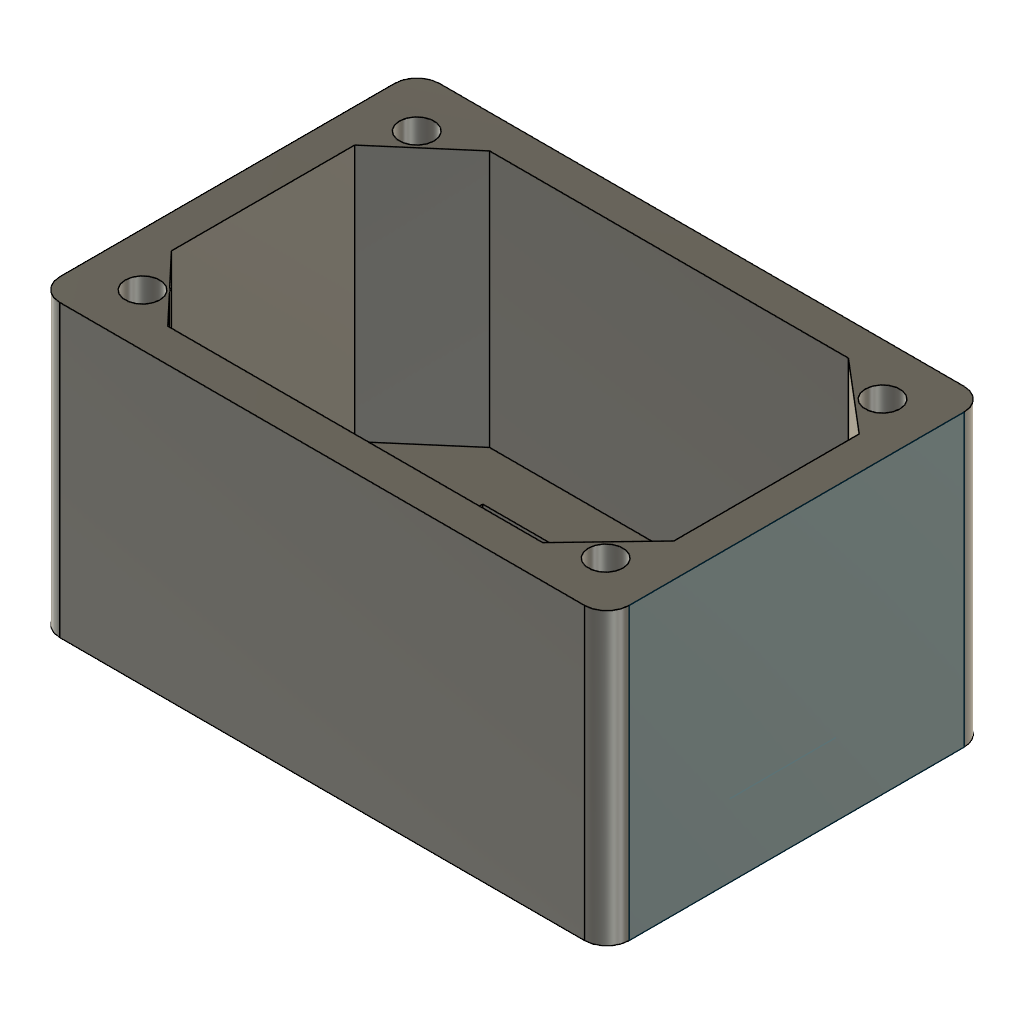
oled keychain (Autodesk Fusion 360 design; units mm, degrees)
Autodesk Fusion 360 part; units mm, degrees
sketch "Sketch1" plane through (0, 0, 0) normal (0, 0, 1) x (1, 0, 0)
  line L0 (0, 0) -> (51, 0)
  line L1 (51, 0) -> (51, 34)
  line L2 (51, 34) -> (0, 34)
  line L3 (0, 34) -> (0, 0)
  dimension "d1" = 51
  dimension "d2" = 34
  constraint horizontal L0
  constraint vertical L1
  constraint horizontal L2
  constraint vertical L3
  constraint coincident L0.start L3.end
  measures "d1" distance of L0.start L0.end
  measures "d2" distance of L0.start L2.end
extrude "Extrude1" add sketch "Sketch1" along normal blind 3
sketch "Sketch2" plane through (0, 0, 3) normal (0, 0, 1) x (-1, 0, 0)
  line L0 (0, -34) -> (0, 0)
  line L1 (0, 0) -> (-51, 0)
  line L2 (-51, 0) -> (-51, -34)
  line L3 (-51, -34) -> (0, -34)
  line L4 (0, -34) -> (-51, -34)
  line L5 (-51, -34) -> (-51, -31)
  line L6 (-51, -31) -> (0, -31)
  line L7 (0, -31) -> (0, -34)
  line L8 (0, 0) -> (-51, 0)
  line L9 (-51, 0) -> (-51, -3)
  line L10 (-51, -3) -> (0, -3)
  line L11 (0, -3) -> (0, 0)
  line L12 (0, -31) -> (-3, -31)
  line L13 (-3, -31) -> (-3, -3)
  line L14 (-3, -3) -> (0, -3)
  line L15 (0, -3) -> (0, -31)
  line L16 (-51, -31) -> (-48, -31)
  line L17 (-48, -31) -> (-48, -3)
  line L18 (-48, -3) -> (-51, -3)
  line L19 (-51, -3) -> (-51, -31)
  dimension "d5" = 3
  dimension "d6" = 3
  constraint horizontal L4
  constraint vertical L5
  constraint horizontal L6
  constraint vertical L7
  constraint coincident L0.start L3.end
  constraint horizontal L8
  constraint vertical L9
  constraint horizontal L10
  constraint vertical L11
  constraint coincident L0.end L1.start
  constraint horizontal L12
  constraint vertical L13
  constraint horizontal L14
  constraint vertical L15
  constraint coincident L10 L13.end
  constraint horizontal L16
  constraint vertical L17
  constraint horizontal L18
  constraint vertical L19
  constraint coincident L10 L17.end
  measures "d5" distance of L0.start L6.end
  measures "d6" distance of L0.end L10.end
extrude "Extrude2" add sketch "Sketch2" along normal blind 23 contours L0 L2 L3 L4 L5 L6 L7 L12 L16 | L0 L6 L10 L12 L13 L14 L15 | L0 L1 L2 L8 L9 L10 L11 L14 L18 | L2 L6 L10 L16 L17 L18 L19
fillet "Fillet1" radius 2 1 edges at (51, 0, 13)
fillet "Fillet2" radius 2 1 edges at (51, 34, 13)
fillet "Fillet3" radius 2 1 edges at (0, 34, 13)
fillet "Fillet4" radius 2 1 edges at (0, 0, 13)
fillet "Fillet5" radius 2 1 edges at (48, 31, 14.5)
fillet "Fillet6" radius 2 1 edges at (48, 3, 14.5)
fillet "Fillet7" radius 2 1 edges at (3, 3, 14.5)
fillet "Fillet8" radius 2 1 edges at (3, 31, 14.5)
sketch "Sketch3" plane through (51, 0, 0) normal (1, 0, 0) x (0, 1, 0)
  line L0 (32, 0) -> (32, 26)
  line L1 (32, 26) -> (2, 26)
  line L2 (2, 26) -> (2, 0)
  line L3 (2, 0) -> (32, 0)
sketch "Sketch4" plane through (0, 0, 3) normal (0, 0, 1) x (-1, 0, 0)
  arc A0 (-5, -31) -> (-3, -29) centre (-5, -29) ccw
  line L0 (-3, -29) -> (-3, -5)
  arc A1 (-3, -5) -> (-5, -3) centre (-5, -5) ccw
  line L1 (-5, -3) -> (-46, -3)
  arc A2 (-46, -3) -> (-48, -5) centre (-46, -5) ccw
  line L2 (-48, -5) -> (-48, -29)
  arc A3 (-48, -29) -> (-46, -31) centre (-46, -29) ccw
  line L3 (-46, -31) -> (-5, -31)
  circle A4 centre (-4.6887, -29.2841) radius 1.75
  circle A5 centre (-46.3362, -29.3549) radius 1.75
  circle A6 centre (-4.7408, -4.6718) radius 1.75
  circle A7 centre (-46.2767, -4.6176) radius 1.75
  dimension "d25" = 3.5
  dimension "d26" = 3.5
  dimension "d27" = 3.5
  dimension "d28" = 3.5
  measures "d25" diameter of A4
  measures "d26" diameter of A5
  measures "d27" diameter of A6
  measures "d28" diameter of A7
extrude "Extrude3" add sketch "Sketch4" along normal blind 23 contours A0 L0 L3 A4 | L2 A3 L3 A5 | A1 L1 A6 | L1 A2 A7 picked at (-4.4586, -29.7393) picked at (-46.6865, -29.6045) picked at (-4.6056, -4.1613) picked at (-46.5061, -4.2491)
hole "Hole1" at (4.6887, 29.2841, 26) direction (0, 0, -1) diameter 3.1 depth 23 tip angle 118
hole "Hole2" at (4.7408, 4.6718, 26) direction (0, 0, -1) diameter 3.1 depth 23 tip angle 118
hole "Hole3" at (46.3362, 29.3549, 26) direction (0, 0, -1) diameter 3.1 depth 23 tip angle 118
hole "Hole4" at (46.2767, 4.6176, 26) direction (0, 0, -1) diameter 3.1 depth 23 tip angle 118
sketch "Sketch5" plane through (0, 0, 3) normal (0, 0, 1) x (-1, 0, 0)
  arc A0 (-47.9987, -4.929) -> (-45.6089, -3) centre (-46.2767, -4.6176) ccw
  arc A1 (-47.9987, -4.929) -> (-48, -5) centre (-46, -5) ccw
  line L0 (-48, -5) -> (-48, -28.8124)
  arc A2 (-45.7394, -31) -> (-48, -28.8124) centre (-46.3362, -29.3549) ccw
  line L1 (-45.7394, -31) -> (-5.0323, -31)
  arc A3 (-3, -28.8249) -> (-5.0323, -31) centre (-4.6887, -29.2841) ccw
  line L2 (-3, -28.8249) -> (-3, -5)
  arc A4 (-3, -5) -> (-3.0035, -4.8819) centre (-5, -5) ccw
  arc A5 (-5.2583, -3) -> (-3.0035, -4.8819) centre (-4.7408, -4.6718) ccw
  line L3 (-5.2583, -3) -> (-45.6089, -3)
  line L4 (-3, -9) -> (-8.6771, -3)
  line L5 (-3, -25.416) -> (-9.4937, -31)
  line L6 (-41.6317, -31) -> (-48, -25.5979)
  line L7 (-42.2584, -3) -> (-48, -9)
  constraint coincident L2 L4.start
  constraint coincident L3 L4.end
  constraint coincident L2 L5.start
  constraint coincident L1 L5.end
  constraint coincident L1 L6.start
  constraint coincident L0 L6.end
  constraint coincident L3 L7.start
  constraint coincident L0 L7.end
extrude "Extrude4" add sketch "Sketch5" along normal blind 23 contours A0 A1 L0 L3 L7 | A5 L3 L4 | L0 A2 L1 L6 | L2 A4 A5 L4 | L1 A3 L2 L5
form "Form1" [no effect]
sketch "Sketch6" plane through (0, 0, 3) normal (0, 0, 1) x (-1, 0, 0)
  line L0 (-42.2584, -3) -> (-48, -9)
  line L1 (-48, -9) -> (-48, -25.5979)
  line L2 (-48, -25.5979) -> (-41.6317, -31)
  line L3 (-41.6317, -31) -> (-9.4937, -31)
  line L4 (-9.4937, -31) -> (-3, -25.416)
  line L5 (-3, -25.416) -> (-3, -9)
  line L6 (-3, -9) -> (-5.7283, -6.1165)
  arc A0 (-6.238, -5.5779) -> (-5.7283, -6.1165) centre (-4.7408, -4.6718) ccw
  line L7 (-6.238, -5.5779) -> (-8.6771, -3)
  line L8 (-8.6771, -3) -> (-42.2584, -3)
  line L9 (-13.5853, -26.299) -> (-38, -26.299)
  line L10 (-38, -26.299) -> (-38, -23.299)
  line L11 (-38, -23.299) -> (-13.5853, -23.299)
  line L12 (-13.5853, -23.299) -> (-13.5853, -26.299)
  dimension "d45" = 3
  constraint horizontal L9
  constraint vertical L10
  constraint horizontal L11
  constraint vertical L12
  measures "d45" distance of L9.start L11.end
extrude "Extrude5" cut sketch "Sketch6" along normal blind 3 and the other way blind 3 contours L9 L10 L11 L12
sketch "Sketch7" plane through (0, 0, 3) normal (0, 0, 1) x (-1, 0, 0)
  line L0 (-13.5853, -23.299) -> (-13.5853, -26.299)
  line L1 (-13.5853, -26.299) -> (-38, -26.299)
  line L2 (-38, -26.299) -> (-38, -23.299)
  line L3 (-38, -23.299) -> (-13.5853, -23.299)
  line L4 (-42.2584, -3) -> (-48, -9)
  line L5 (-48, -9) -> (-48, -25.5979)
  line L6 (-48, -25.5979) -> (-41.6317, -31)
  line L7 (-41.6317, -31) -> (-9.4937, -31)
  line L8 (-9.4937, -31) -> (-3, -25.416)
  line L9 (-3, -25.416) -> (-3, -9)
  line L10 (-3, -9) -> (-5.7283, -6.1165)
  arc A0 (-6.238, -5.5779) -> (-5.7283, -6.1165) centre (-4.7408, -4.6718) ccw
  line L11 (-6.238, -5.5779) -> (-8.6771, -3)
  line L12 (-8.6771, -3) -> (-42.2584, -3)
  line L13 (-13.5232, -12.253) -> (-38, -12.253)
  line L14 (-38, -12.253) -> (-38, -9.253)
  line L15 (-38, -9.253) -> (-13.5232, -9.253)
  line L16 (-13.5232, -9.253) -> (-13.5232, -12.253)
  dimension "d50" = 3
  constraint horizontal L13
  constraint vertical L14
  constraint horizontal L15
  constraint vertical L16
  measures "d50" distance of L13.start L15.end
extrude "Extrude6" cut sketch "Sketch7" along normal blind 0 and the other way blind 3 contours L13 L14 L15 L16
sketch "Sketch8" plane through (51, 0, 0) normal (1, 0, 0) x (0, 1, 0)
